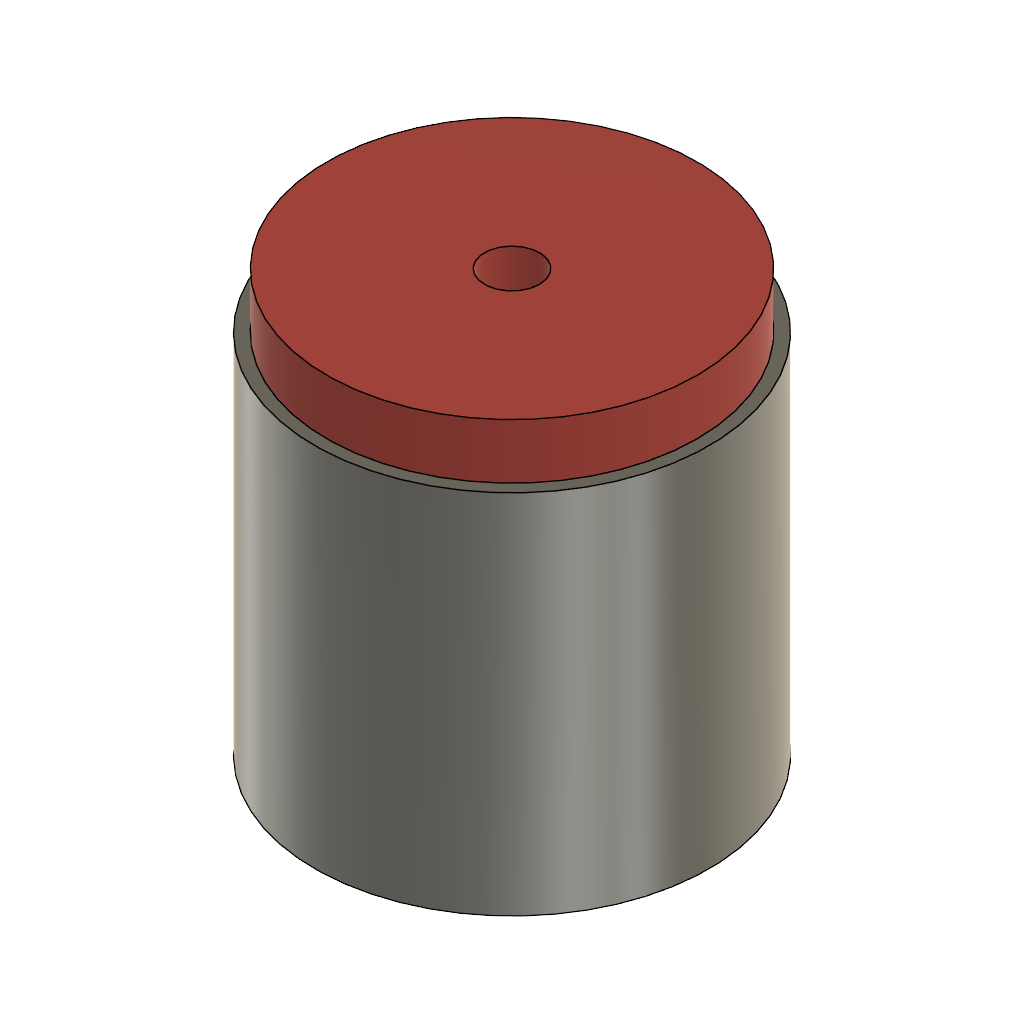
Card_Drive_Wheel_Connector (Autodesk Fusion 360 design; units mm, degrees)
Autodesk Fusion 360 part; units mm, degrees
sketch "Çizim1" plane through (0, 0, 0) normal (0, 0, 1) x (1, 0, 0)
  circle A0 centre (0, 0) radius 8.6
  dimension "d1" = 17.2
  constraint coincident A0.centre origin
  measures "d1" diameter of A0
extrude "Ekstrüzyon1" add sketch "Çizim1" along normal blind 20 makes body 1
sketch "Çizim2" plane through (0, 0, 20) normal (0, 0, 1) x (-1, 0, 0)
  circle A0 centre (0, 0) radius 8.6
  circle A1 centre (0, 0) radius 10.1
  dimension "d4" = 20.2
  constraint concentric A0 A1
  measures "d4" diameter of A1
extrude "Ekstrüzyon2" add sketch "Çizim2" along normal blind 3 contours A0 | A1 bodies 1
sketch "Çizim3" plane through (0, 0, 23) normal (0, 0, 1) x (-1, 0, 0)
  circle A0 centre (0, 0) radius 10.1
  circle A1 centre (0, 0) radius 1.5
  dimension "d7" = 3
  constraint coincident A0.centre A1.centre
  measures "d7" diameter of A1
extrude "Ekstrüzyon3" cut sketch "Çizim3" against normal blind 23 contours A1 bodies 1
sketch "Çizim4" plane through (0, 0, 0) normal (0, 0, -1) x (1, 0, 0)
  circle A0 centre (0, 0) radius 1.5
  circle A1 centre (0, 0) radius 8.6
  circle A2 centre (0, 0) radius 10.75
  dimension "d10" = 21.5
  constraint concentric A0 A2
  measures "d10" diameter of A2
extrude "Ekstrüzyon4" add sketch "Çizim4" against normal blind 20 separate body contours A2 makes body 2
equation "d4 = 17.2 mm + 3 mm"
named bodies: "Roller_Connector", "Roller"
